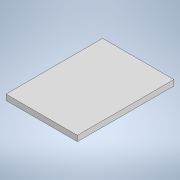
# Autodesk Inventor part: intaritura_partea_din_spate_cutie_tevi_cu_usa
Saved by Autodesk Inventor 2022.6 (Build 266554000, 554)
## iProperties
Created: 2026-11-01
Part Number: intaritura_partea_din_spate_cutie_tevi_cu_usa
Material: Generic
Document SubType Name: Modeling
Designer: Dragos Macovei
Density: 1 g/cm^3
Appearance: Default
Author: Dragos Macovei
Autodesk Inventor part; units mm, degrees
ref_plane "YZ Plane" through (0, 0, 0) normal (1, 0, 0) x (0, 1, 0)
ref_plane "XZ Plane" through (0, 0, 0) normal (0, 1, 0) x (-1, 0, 0)
ref_plane "XY Plane" through (0, 0, 0) normal (0, 0, 1) x (1, 0, 0)
sketch "Sketch1" plane through (0, 0, 0) normal (0, 1, 0) x (-1, 0, 0)
  line L0 (0, 0) -> (232, 0)
  line L1 (232, 0) -> (232, 314)
  line L2 (232, 314) -> (0, 314)
  line L3 (0, 314) -> (0, 0)
  dimension "d0" = 314
  dimension "d1" = 232
  constraints: 8 end point, 2 parallel, 1 horizontal, 1 perpendicular
  measures "d0" distance of L0.end L1.end
  measures "d1" distance of L1.end L2.end
extrude "Extrusion1" add sketch "Sketch1" along normal blind 18
body "Solid1"
